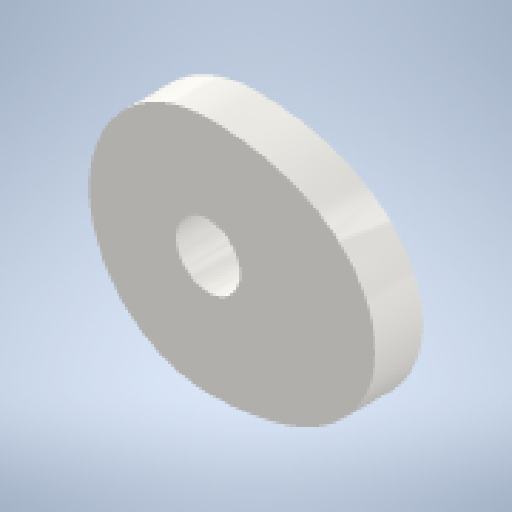
# Autodesk Inventor part: Disc Cam
Saved by Autodesk Inventor 2025.2 (Build 292293000, 293)
## iProperties
CustomPartVersion: 1
Created: 2025-05-16
Part Number: Disc Cam
Material: Stainless Steel, Austenitic
Document SubType Name: Modeling
Designer: laura
Manufacturer: Standard
Standards Organization: Custom
Density: 1 g/cm^3
Appearance: Steel
Author: laura
Autodesk Inventor part; units mm, degrees
ref_plane "YZ Plane" through (0, 0, 0) normal (1, 0, 0) x (0, 1, 0)
ref_plane "XZ Plane" through (0, 0, 0) normal (0, 1, 0) x (-1, 0, 0)
ref_plane "XY Plane" through (0, 0, 0) normal (0, 0, 1) x (1, 0, 0)
sketch "Main Sketch" plane through (0, 0, 0) normal (0, 0, 1) x (1, 0, 0)
  spline S0 degree 5 poles (0, 15) (0.4837, 15.0036) (1.352, 14.9894) (2.8243, 14.9294) (4.4228, 14.7985) (6.6429, 14.5017) (8.6078, 14.1039) (10.6303, 13.5445) (12.5388, 12.833) (14.3436, 11.9598) (16.0112, 10.9222) (17.5234, 9.722) (18.8538, 8.3682) (19.9795, 6.8756) (20.8789, 5.2654) (21.5344, 3.5631) (21.933, 1.7976) (22.0667, 0) (21.933, -1.7976) (21.5344, -3.5631) (20.8789, -5.2654) (19.9795, -6.8756) (18.8538, -8.3682) (17.5234, -9.722) (16.0113, -10.9222) (14.3435, -11.9599) (12.539, -12.833) (10.6298, -13.5445) (8.6089, -14.1038) (6.5696, -14.5162) (4.3943, -14.8011) (2.4582, -14.9582) (0.0461, -15.032) (-1.3863, -14.9811) (-3.1093, -14.7221) (-4.6253, -14.3102) (-6.1227, -13.7404) (-7.5185, -13.0262) (-8.8419, -12.1685) (-10.0641, -11.1778) (-11.1779, -10.0645) (-12.1685, -8.841) (-13.0261, -7.5206) (-13.7408, -6.1178) (-14.305, -4.648) (-14.7125, -3.1272) (-14.9588, -1.5722) (-15.0412, 0) (-14.9588, 1.5722) (-14.7125, 3.1272) (-14.305, 4.648) (-13.7408, 6.1178) (-13.0261, 7.5206) (-12.1685, 8.841) (-11.178, 10.0645) (-10.0639, 11.1778) (-8.8423, 12.1685) (-7.5175, 13.0263) (-6.1249, 13.7403) (-4.6912, 14.2836) (-3.2239, 14.6951) (-1.8898, 14.9055) (-1.043, 14.9775) (-0.4082, 14.997) (0, 15) knots 0 0 0 0 0 0 0.022339 0.037144 0.055567 0.073834 0.091923 0.109827 0.127549 0.145099 0.162488 0.179727 0.196832 0.213821 0.230715 0.247543 0.264337 0.281131 0.297959 0.314854 0.331842 0.348947 0.366187 0.383575 0.401125 0.418848 0.436752 0.45484 0.473107 0.49153 0.509477 0.52691 0.543792 0.560096 0.575807 0.591518 0.607229 0.62294 0.63865 0.654361 0.670072 0.685783 0.701494 0.717205 0.732916 0.748626 0.764337 0.780048 0.795759 0.81147 0.827181 0.842892 0.858602 0.874313 0.890024 0.905735 0.921446 0.937157 0.952867 0.968578 0.981147 1 1 1 1 1 1
  point P0 (4.4125, 14.7727)
  point P1 (6.5608, 14.4803)
  point P2 (8.6448, 14.0568)
  point P3 (10.6483, 13.4916)
  point P4 (12.555, 12.7744)
  point P5 (14.3475, 11.8978)
  point P6 (16.0052, 10.8584)
  point P7 (17.5055, 9.6589)
  point P8 (18.8243, 8.3084)
  point P9 (19.9386, 6.8223)
  point P10 (20.8278, 5.2216)
  point P11 (21.475, 3.5318)
  point P12 (21.8681, 1.7813)
  point P13 (22, 0)
  point P14 (21.8681, -1.7813)
  point P15 (21.475, -3.5318)
  point P16 (20.8278, -5.2216)
  point P17 (19.9386, -6.8223)
  point P18 (18.8243, -8.3084)
  point P19 (17.5055, -9.6589)
  point P20 (16.0052, -10.8584)
  point P21 (14.3475, -11.8978)
  point P22 (12.555, -12.7744)
  point P23 (10.6483, -13.4916)
  point P24 (8.6448, -14.0568)
  point P25 (6.5608, -14.4803)
  point P26 (4.4125, -14.7727)
  point P27 (2.2183, -14.9438)
  point P28 (0, -15)
  point P29 (-1.5679, -14.9178)
  point P30 (-3.1187, -14.6722)
  point P31 (-4.6353, -14.2658)
  point P32 (-6.101, -13.7032)
  point P33 (-7.5, -12.9904)
  point P34 (-8.8168, -12.1353)
  point P35 (-10.037, -11.1472)
  point P36 (-11.1472, -10.037)
  point P37 (-12.1353, -8.8168)
  point P38 (-12.9904, -7.5)
  point P39 (-13.7032, -6.101)
  point P40 (-14.2658, -4.6353)
  point P41 (-14.6722, -3.1187)
  point P42 (-14.9178, -1.5679)
  point P43 (-15, 0)
  point P44 (-14.9178, 1.5679)
  point P45 (-14.6722, 3.1187)
  point P46 (-14.2658, 4.6353)
  point P47 (-13.7032, 6.101)
  point P48 (-12.9904, 7.5)
  point P49 (-12.1353, 8.8168)
  point P50 (-11.1472, 10.037)
  point P51 (-10.037, 11.1472)
  point P52 (-8.8168, 12.1353)
  point P53 (-7.5, 12.9904)
  point P54 (-6.101, 13.7032)
  point P55 (-4.6353, 14.2658)
  point P56 (-3.1187, 14.6722)
  point P57 (-1.5679, 14.9178)
  constraints: 60 other
extrude "Cam" add sketch "Main Sketch" along normal blind 6
sketch "Sketch2" plane through (0, 0, 6) normal (0, 0, 1) x (1, 0, 0)
  circle A0 centre (0, 0) radius 4
  dimension "d4" = 8
  constraints: 1 centre point, 1 coincident
  measures "d4" diameter of A0
extrude "Extrusion2" cut sketch "Sketch2" against normal through all
equation "\"d4\" = d_eje"
equation "\"d_eje\" = 8"
body "Solid1"
